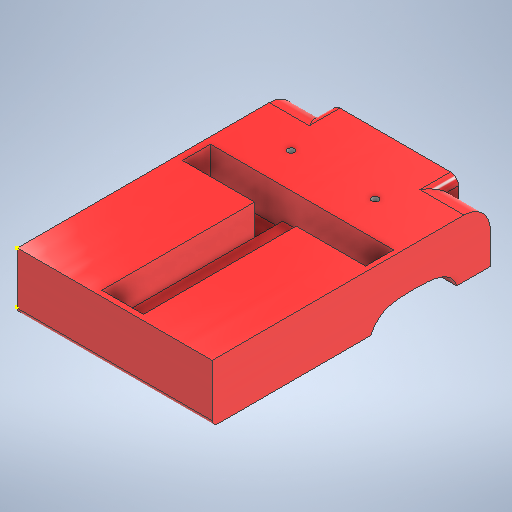
# Autodesk Inventor part: Body AGV
Saved by Autodesk Inventor 2025 (Build 290162000, 162)
## iProperties
Created: 2026-01-01
Part Number: Body AGV
Material: Generic
Document SubType Name: Modeling
Designer: novsa
Density: 1 g/cm^3
Appearance: Default
Mass: 973.441 g
Surface Area: 975.684 cm^2
Volume: 973.441 cm^3
Author: novsa
Autodesk Inventor part; units mm, degrees
ref_plane "YZ Plane" through (0, 0, 0) normal (1, 0, 0) x (0, 1, 0)
ref_plane "XZ Plane" through (0, 0, 0) normal (0, 1, 0) x (-1, 0, 0)
sketch "Sketch1" plane through (0, 0, 0) normal (0, 1, 0) x (-1, 0, 0)
  line L0 (0, 0) -> (-140, 0)
  line L1 (-140, 0) -> (-140, -200)
  line L2 (-140, -200) -> (0, -200)
  line L3 (0, -200) -> (0, 0)
  dimension "d0" = 140
  dimension "d1" = 200
  constraints: 8 end point, 2 parallel, 1 horizontal, 1 perpendicular
  measures "d0" distance of L2.end L1.end
  measures "d1" distance of L0.end L1.end
extrude "Extrusion1" add sketch "Sketch1" along normal blind 4.5
sketch "Sketch2" plane through (0, 4.5, 0) normal (0, 1, 0) x (1, 0, 0)
  line L0 (0, 0) -> (140, 0) projected
  line L1 (0, 200) -> (0, 0) projected
  line L2 (140, 0) -> (140, 200) projected
  line L3 (0, 200) -> (0, 180)
  line L4 (140, 200) -> (0, 200) projected
  line L5 (140, 200) -> (140, 180)
  line L6 (23.779, 89.613) -> (0, 89.613)
  line L7 (0, 89.613) -> (0, 20)
  line L8 (0, 180) -> (23.779, 180)
  line L9 (23.779, 180) -> (23.779, 110.387)
  line L10 (23.779, 110.387) -> (0, 110.387)
  line L11 (0, 110.387) -> (0, 180)
  line L12 (116.221, 89.613) -> (140, 89.613)
  line L13 (140, 89.613) -> (140, 20)
  line L14 (140, 180) -> (116.221, 180)
  line L15 (116.221, 180) -> (116.221, 110.387)
  line L16 (116.221, 110.387) -> (140, 110.387)
  line L17 (140, 110.387) -> (140, 180)
  dimension "d4" = 20
  dimension "d6" = 20
  dimension "d7" = 20
  dimension "d8" = 23.779
  dimension "d10" = 23.779
  dimension "d11" = 69.613
  dimension "d12" = 23.779
  constraints: 28 end point, 4 parallel, 4 point on line, 2 horizontal, 2 perpendicular
  measures "d4" distance of L0.start L7.end
  measures "d6" distance of L1.start L3.end
  measures "d7" distance of L2.end L5.end
  measures "d8" distance of L6.end L6.start
  measures "d10" distance of L9.end L10.end
  measures "d11" distance of L8.end L9.end
  measures "d12" distance of L12.start L12.end
extrude "Extrusion2" add sketch "Sketch2" along normal blind 37
sketch "Sketch9" plane through (0, 0, -200) normal (-1, 0, 0) x (0, 0, 1)
  line L0 (0, 0) -> (200, 0) projected
  line L1 (22.6849, 0) -> (25.1791, 10.2938) construction
  line L2 (25.1791, 10.2938) -> (43.2562, 16.5054) construction
  line L3 (43.2562, 16.5054) -> (63.5554, 16.5054) construction
  line L4 (63.5554, 16.5054) -> (81.4004, 10.2938) construction
  line L5 (81.4004, 10.2938) -> (84.9338, 0) construction
  spline S0 degree 4 poles (22.6849, 0) (25.1791, 10.2938) (43.2562, 16.5054) (63.5554, 16.5054) (81.4004, 10.2938) (84.9338, 0) knots 1 1 1 1 1 2 3 3 3 3 3
  line L6 (114.9001, 0.0762) -> (117.5836, 10.2938) construction
  line L7 (117.5836, 10.2938) -> (134.9681, 16.5054) construction
  line L8 (134.9681, 16.5054) -> (155.9763, 16.5054) construction
  line L9 (155.9763, 16.5054) -> (172.7476, 10.2938) construction
  line L10 (172.7476, 10.2938) -> (177.149, 0.0762) construction
  spline S1 degree 4 poles (114.9001, 0.0762) (117.5836, 10.2938) (134.9681, 16.5054) (155.9763, 16.5054) (172.7476, 10.2938) (177.149, 0.0762) knots 1 1 1 1 1 2 3 3 3 3 3
  point P0 (84.9338, 0)
  constraints: 2 horizontal, 1 point on line, 6 other
extrude "Extrusion3" cut sketch "Sketch9" against normal blind 23.5
sketch "Sketch12" plane through (140, 4.5, -180) normal (1, 0, 0) x (0, 0, -1)
  line L0 (-180, -4.5) -> (20, -4.5) projected
  line L1 (-4.2568, -4.5) -> (-6.4575, 2.5737) construction
  line L2 (-6.4575, 2.5737) -> (-15.8892, 8.8615) construction
  line L3 (-15.8892, 8.8615) -> (-32.2374, 8.8615) construction
  line L4 (-32.2374, 8.8615) -> (-51.1007, 8.8615) construction
  line L5 (-51.1007, 8.8615) -> (-60.5324, 5.4032) construction
  line L6 (-60.5324, 5.4032) -> (-66.1914, -4.5) construction
  spline S0 degree 4 poles (-4.2568, -4.5) (-6.4575, 2.5737) (-15.8892, 8.8615) (-32.2374, 8.8615) (-51.1007, 8.8615) (-60.5324, 5.4032) (-66.1914, -4.5) knots 1 1 1 1 1 2 3 4 4 4 4 4
  point P0 (-92.5265, -4.5)
  constraints: 2 horizontal, 2 point on line, 3 other
extrude "Extrusion6" cut sketch "Sketch12" against normal blind 23.5
sketch "Sketch13" plane through (0, 4.5, 0) normal (0, 1, 0) x (1, 0, 0)
  point P0 (0, 0)
sketch "Sketch14" plane through (0, 4.5, 0) normal (0, 1, 0) x (1, 0, 0)
  point P0 (0, 0)
sketch "Sketch15" plane through (0, 4.5, 0) normal (0, 1, 0) x (1, 0, 0)
  point P0 (0, 0)
sketch "Sketch18" plane through (0, 4.5, 0) normal (0, 1, 0) x (1, 0, 0)
  point P0 (0, 0)
ref_plane "Work Plane2" through (0, 24.25, 0) normal (0, 1, 0) x (1, 0, 0)
sketch "Sketch22" plane through (0, 24.25, 0) normal (0, 1, 0) x (1, 0, 0)
  line L0 (140, 0) -> (140, 18) projected
  line L1 (140, 0) -> (0, 0)
  line L2 (0, 22.8041) -> (140, 22.8041)
  line L3 (140, 22.8041) -> (140, 0)
  line L4 (0, 0) -> (0, 22.8041)
  line L5 (0, 115.0662) -> (0, 0) projected
  point P0 (0, 23.6036)
  constraints: 8 end point, 2 point on line, 1 horizontal, 1 parallel
extrude "Extrusion7" add sketch "Sketch22" against normal blind 24
fillet "Fillet6" radius 4 1 edges at (70, 0, 0)
sketch "Sketch36" plane through (0, 41.5, 0) normal (0, 1, 0) x (1, 0, 0)
  point P0 (0, 0)
sketch "Sketch39" plane through (0, 41.5, 0) normal (0, 1, 0) x (1, 0, 0)
  line L0 (0, 4) -> (140, 4) projected
  line L1 (56.6444, 4) -> (86.6444, 4)
  line L2 (86.6444, 4) -> (86.6444, 134)
  line L3 (86.6444, 134) -> (56.6444, 134)
  line L4 (56.6444, 134) -> (56.6444, 4)
  line L5 (116.5, 113.8086) -> (140, 113.8086) projected
  line L6 (4.8243, 134) -> (136.4373, 134)
  line L7 (136.4373, 134) -> (136.4373, 113.8086)
  line L8 (136.4373, 113.8086) -> (4.8243, 113.8086)
  line L9 (4.8243, 113.8086) -> (4.8243, 134)
  point P0 (0, 0)
  point P1 (86.6444, 113.8086)
  point P2 (56.6444, 113.8086)
  dimension "d60" = 30
  dimension "d61" = 130
  dimension "d66" = 131.613
  dimension "d67" = 20.1913
  constraints: 16 end point, 4 parallel, 2 horizontal, 2 perpendicular, 2 point on line
  measures "d60" distance of L3.end L2.end
  measures "d61" distance of L1.end L2.end
  measures "d66" distance of L7.end L8.end
  measures "d67" distance of L8.end L6.start
extrude "Extrusion14" cut sketch "Sketch39" against normal blind 22 contours L4 L8 L2 L0 | L4 L3 L2 L8
extrude "Extrusion15" cut sketch "Sketch39" against normal blind 27 contours L8 L9 L6 L4 | L2 L6 L7 L5 L8
sketch "Sketch40" plane through (140, 0, -200) normal (0, 0, -1) x (-1, 0, 0)
  line L0 (135.1757, 41.5) -> (3.5627, 41.5) projected
  line L1 (25.9347, 41.5) -> (116.9347, 41.5)
  line L2 (116.9347, 41.5) -> (116.9347, 20.5)
  line L3 (116.9347, 20.5) -> (25.9347, 20.5)
  line L4 (25.9347, 20.5) -> (25.9347, 41.5)
  point P0 (140, 0)
  dimension "d68" = 91
  dimension "d69" = 21
  constraints: 8 end point, 2 parallel, 1 horizontal, 1 perpendicular, 1 point on line
  measures "d68" distance of L2.end L3.end
  measures "d69" distance of L3.end L1.start
extrude "Extrusion16" add sketch "Sketch40" along normal blind 3
fillet "Fillet10" radius 19 2 edges at (127.0327, 41.5, -200) (11.5327, 41.5, -200)
fillet "Fillet11" radius 5.75 5 edges at (114.0653, 41.5, -190.5) (114.0653, 41.5, -201.5) (23.0653, 41.5, -190.5) (23.0653, 41.5, -201.5) (68.5653, 20.5, -203)
sketch "Sketch42" plane through (0, 41.5, 0) normal (0, 1, 0) x (1, 0, 0)
  circle A0 centre (69.9038, 39.2734) radius 2.5
  circle A1 centre (37.7321, 158.9583) radius 2.5
  circle A2 centre (98.0846, 158.9583) radius 2.5
  point P0 (0, 0)
  dimension "d81" = 5
  dimension "d82" = 5
  dimension "d83" = 5
  constraints: 3 centre point
  measures "d81" diameter of A0
  measures "d82" diameter of A1
  measures "d83" diameter of A2
extrude "Extrusion18" cut sketch "Sketch42" against normal blind 59.75
body "Solid1"
